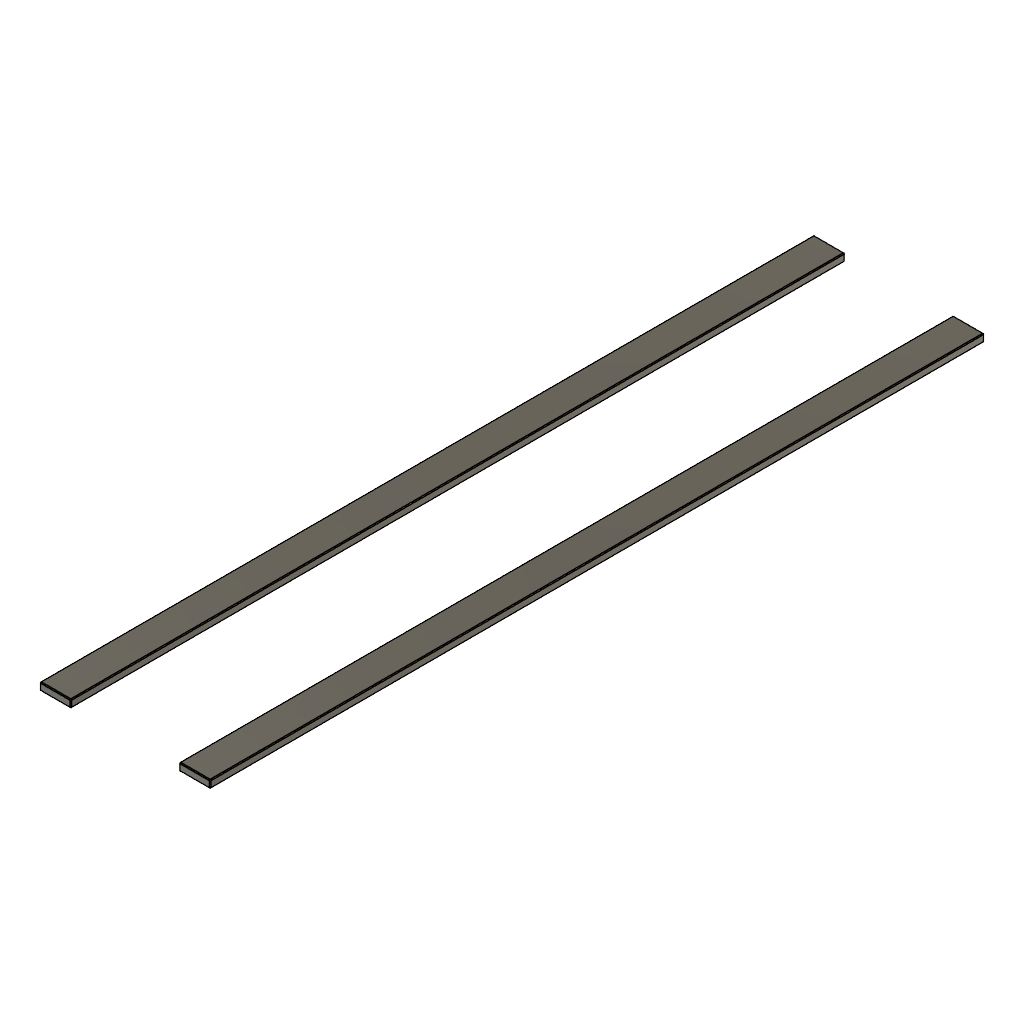
capstone_1 (Autodesk Fusion 360 design; units mm, degrees)
part number: 2026-10-12-13-46-10-934
part number: 2026-10-12-15-33-25-098
part number: 2026-10-12-15-34-43-585
part number: 2026-10-12-15-35-11-075
part number: 2026-10-12-15-35-28-845
part number: 2026-10-12-15-35-36-615
Autodesk Fusion 360 part; units mm, degrees
sketch "스케치1" plane through (0, 0, 0) normal (0, 1, 0) x (1, 0, 0)
  line L0 (-50, -50) -> (50, -50)
  line L1 (50, -50) -> (50, 50)
  line L2 (50, 50) -> (-50, 50)
  line L3 (-50, 50) -> (-50, -50)
  constraint horizontal L0
  constraint vertical L1
  constraint horizontal L2
  constraint vertical L3
sketch "스케치2" plane through (0, 0, 0) normal (0, 0, 1) x (1, 0, 0)
sketch "스케치3" plane through (0, 0, 0) normal (0, 1, 0) x (1, 0, 0)
sketch "스케치4" plane through (0, 0, 0) normal (0, 0, 1) x (1, 0, 0)
  line L0 (150, 150) -> (-90, 150)
  line L1 (-90, 150) -> (-90, -150)
  line L2 (-90, -150) -> (150, -150)
  line L3 (150, -150) -> (150, 150)
  constraint horizontal L0
  constraint vertical L1
  constraint horizontal L2
  constraint vertical L3
sketch "스케치5" plane through (0, 0, -20) normal (0, 0, -1) x (1, 0, 0)
  line L0 (150, -150) -> (150, 150)
  line L1 (150, 150) -> (-90, 150)
  line L2 (-90, 150) -> (-90, -150)
  line L3 (-90, -150) -> (150, -150)
  circle A0 centre (290, -120) radius 10
sketch "스케치6" plane through (0, 0, -20) normal (0, 0, -1) x (1, 0, 0)
sphere "구 기본 형상1" add diameter 100 placed x (1, 0, 0) y (0, -1, 0) z (0, 0, -1) at (240, 10, -20) makes body 1
move_body "면 이동2" bodies 1 to x (1, 0, 0) y (0, 1, 0) z (0, 0, 1) at (-210, -260, 0) on bodies 1
delete_face "면 삭제3" 1 faces at (77.4037, -238.1809, -30.6393) on bodies 1
sketch "스케치10" plane through (0, 0, 0) normal (0, 0, 1) x (1, 0, 0)
  line L0 (-150, -150) -> (300, -150)
  line L1 (300, -150) -> (300, 200)
  line L2 (300, 200) -> (-150, 200)
  line L3 (-150, 200) -> (-150, -150)
  constraint horizontal L0
  constraint vertical L1
  constraint horizontal L2
  constraint vertical L3
sketch "스케치11" plane through (0, 0, 5) normal (0, 0, 1) x (-1, 0, 0)
sketch "스케치12" plane through (0, 0, 5) normal (0, 0, 1) x (-1, 0, 0)
sketch "스케치1 (2)" plane through (0, 0, 5) normal (0, 0, 1) x (-1, 0, 0) in component "중심기"
  line L0 (350, -210) -> (279.9087, -210)
  line L1 (279.9087, -210) -> (279.9087, 290)
  line L2 (279.9087, 290) -> (350, 290)
  line L3 (350, 290) -> (350, -210)
  dimension "d25" = 500
  constraint horizontal L0
  constraint vertical L1
  constraint horizontal L2
  constraint vertical L3
  measures "d25" distance of L0.start L2.end
extrude "돌출1" add sketch "스케치1 (2)" along normal blind 5 separate body makes body 2 in component "중심기"
extrude "돌출2" cut 1 faces at (-350, -123.3333, 6.6667) along direction (1, 0, 0) blind 50 on bodies 2 bodies 2 in component "중심기"
fillet "필렛1" radius 0.5 6 faces at (-293.3029, 43.3333, 10) (-293.3029, 210, 6.6667) (-279.9087, 43.3333, 6.6667) (-300, -123.3333, 6.6667) (-293.3029, 43.3333, 5) (-286.6058, -290, 6.6667) on bodies 2 in component "중심기"
copy_body "본체 복사하여 붙여넣기1" bodies 2 makes body 3 in component "중심기"
move_body "이동1" bodies 3 to x (1, 0, 0) y (0, 1, 0) z (0, 0, 1) at (-90, 0, 0) in component "중심기"
component "등" placed x (1, 0, 0) y (0, 1, 0) z (0, 0, 1) at (0, 0, 0)
component "관" placed x (1, 0, 0) y (0, 1, 0) z (0, 0, 1) at (0, 0, 0)
component "중심기" placed x (1, 0, 0) y (0, 1, 0) z (0, 0, 1) at (0, 0, 0)
component "아" placed x (1, 0, 0) y (0, 1, 0) z (0, 0, 1) at (0, 0, 0)
component "우산" placed x (1, 0, 0) y (0, 1, 0) z (0, 0, 1) at (0, 0, 0)
